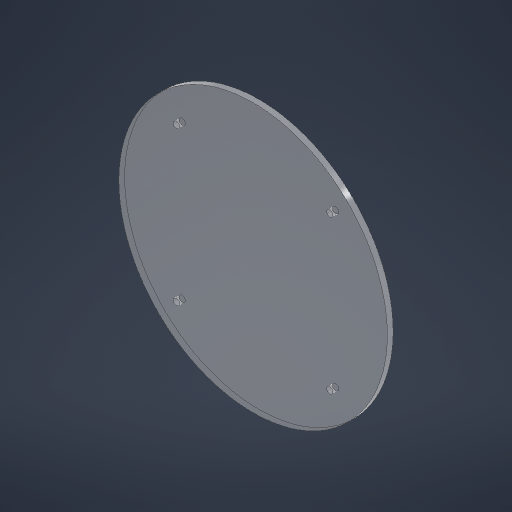
# Autodesk Inventor part: Chasis_Placa_1
Saved by Autodesk Inventor 2026.2 (Build 302298010, 298A)
## iProperties
Created: 2026-10-27
Part Number: Chasis_Placa_1
Material: Policarbonato, claro
Document SubType Name: Modeling
Designer: efrey
Density: 1.2 g/cm^3
Appearance: Policarbonato - Claro
Author: efrey
Autodesk Inventor part; units mm, degrees
ref_plane "YZ Plane" through (0, 0, 0) normal (1, 0, 0) x (0, 1, 0)
ref_plane "XZ Plane" through (0, 0, 0) normal (0, 1, 0) x (-1, 0, 0)
ref_plane "XY Plane" through (0, 0, 0) normal (0, 0, 1) x (1, 0, 0)
sketch "Boceto1" plane through (0, 0, 0) normal (0, 0, 1) x (1, 0, 0)
  circle A0 centre (0, 0) radius 70
  circle A1 centre (40, -40) radius 1.6
  circle A2 centre (-40, -40) radius 1.6
  circle A3 centre (40, 40) radius 1.6
  circle A4 centre (-40, 40) radius 1.6
  dimension "d0" = 140
  dimension "d4" = 3.2
  dimension "d6" = 40
  dimension "d7" = 40
  dimension "d8" = 3.2
  dimension "d9" = 3.2
  dimension "d10" = 3.2
  dimension "d11" = 40
  dimension "d12" = 40
  dimension "d13" = 40
  dimension "d14" = 40
  dimension "d15" = 40
  dimension "d16" = 40
  constraints: 5 centre point, 1 coincident
  measures "d0" diameter of A0
  measures "d4" diameter of A1
  measures "d6" horizontal distance of A0.centre A1.centre
  measures "d7" horizontal distance of A0.centre A1.centre
  measures "d8" diameter of A2
  measures "d9" diameter of A3
  measures "d10" diameter of A4
  measures "d11" horizontal distance of A0.centre A3.centre
  measures "d12" horizontal distance of A0.centre A3.centre
  measures "d13" horizontal distance of A0.centre A4.centre
  measures "d14" horizontal distance of A0.centre A4.centre
  measures "d15" horizontal distance of A0.centre A2.centre
  measures "d16" horizontal distance of A0.centre A2.centre
extrude "Extrusión1" add sketch "Boceto1" along normal mid plane 3
